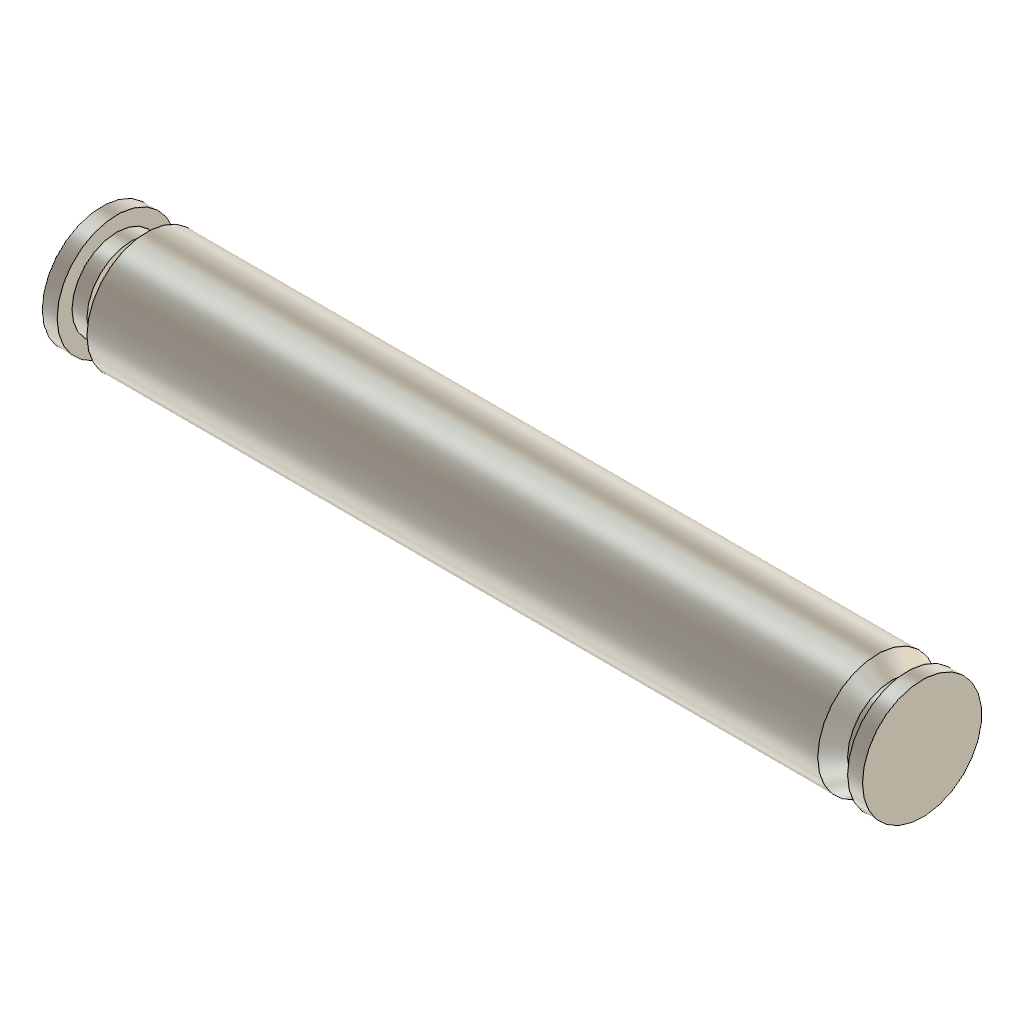
Full_V2_assembly_v81 (Autodesk Fusion 360 archive; units mm, degrees)
design "Foot_pin"
Autodesk Fusion 360 part; units mm, degrees
sketch "Sketch1" plane through (0, 0, 0) normal (1, 0, 0) x (0, 1, 0)
  circle A0 centre (0, 0) radius 4
  circle A1 centre (0, 0) radius 3
  dimension "d1" = 8
  dimension "d2" = 6
  constraint coincident A0.centre A1.centre
  measures "d1" diameter of A0
  measures "d2" diameter of A1
extrude "Extrude1" add sketch "Sketch1" along normal blind 55 contours A0 | A1
extrude "Extrude2" cut sketch "Sketch1" along normal blind 54
extrude "Extrude3" add sketch "Sketch1" along normal blind 53
extrude "Extrude4" cut sketch "Sketch1" along normal blind 2
extrude "Extrude5" add sketch "Sketch1" along normal blind 1
chamfer "Chamfer1" distance 1 angle 45 2 edges at (2, -3.7293, -1.4465) (53, -3.7293, -1.4465) tangent chain off

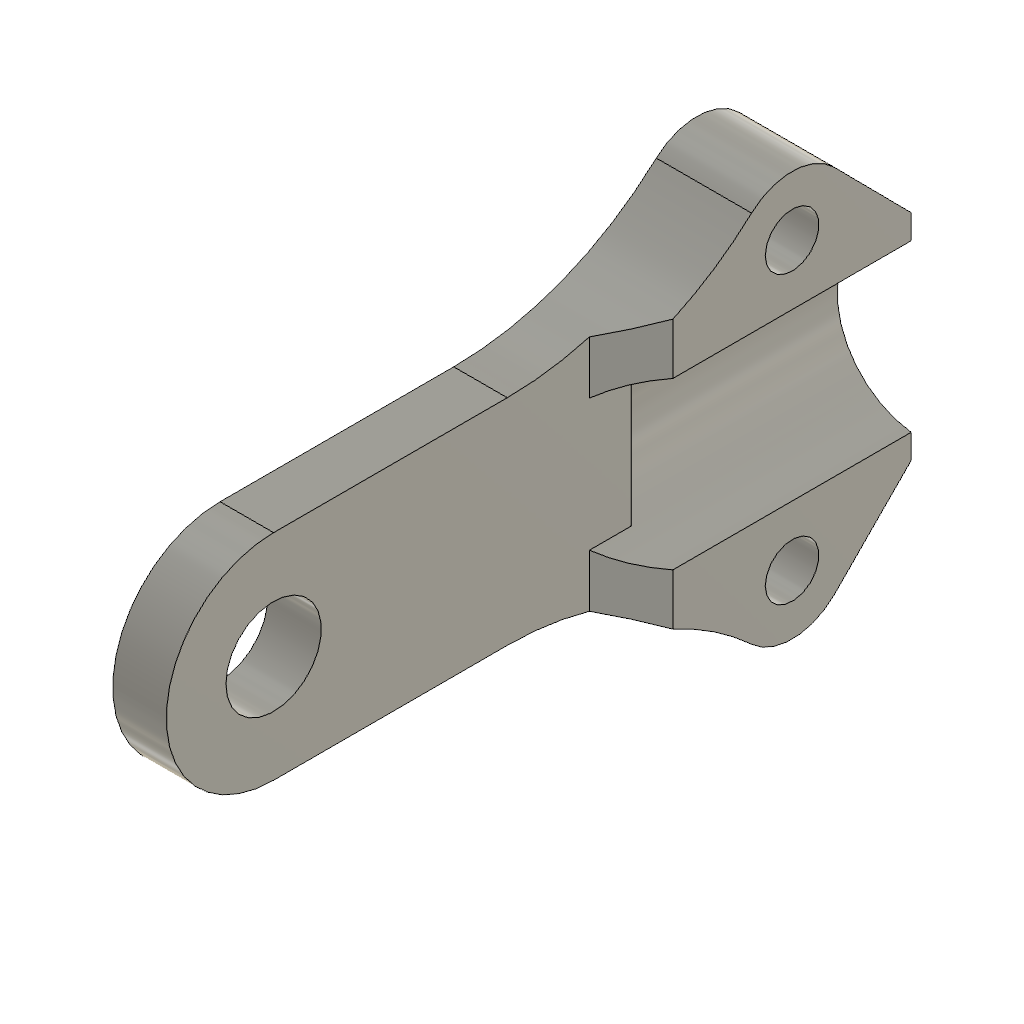
design "push_rod_cap"
Autodesk Fusion 360 part; units mm, degrees
sketch "Sketch1" plane through (0, 0, 0) normal (1, 0, 0) x (0, 1, 0)
  line L0 (30, -9) -> (30, 9)
  line L1 (0, -9) -> (0, 9)
  line L2 (30, 9) -> (36.445163, 15.516124)
  circle A0 centre (40, 12) radius 5
  circle A1 centre (40, 12) radius 2.25
  line L3 (50, 9) -> (50, -9)
  circle A2 centre (0, 0) radius 9
  line L4 (40, -9) -> (40, -12)
  line L5 (30, -9) -> (36.445163, -15.516124)
  line L6 (0, 9) -> (50, 9)
  line L7 (50, -9) -> (43.554837, -15.516124)
  circle A3 centre (0, 0) radius 4
  line L8 (50, 9) -> (50, -9)
  line L9 (50, 9) -> (43.554837, 15.516124)
  circle A4 centre (40, -12) radius 2.25
  line L10 (30, 9) -> (50, 9)
  circle A5 centre (40, -12) radius 5
  line L11 (50, -9) -> (30, -9)
  line L12 (50, -9) -> (0, -9)
  line L13 (40, 9) -> (40, 12)
  dimension "d1" = 8
  dimension "d2" = 18
  dimension "d3" = 50
  dimension "d4" = 4.5
  dimension "d5" = 20
  dimension "d6" = 3
  dimension "d7" = 3
  dimension "d8" = 4.5
  dimension "d9" = 10
  dimension "d10" = 10
  constraint coincident A2.centre A3.centre
  constraint concentric A2 A3
  constraint horizontal L6
  constraint vertical L8
  constraint horizontal L12
  constraint vertical L1
  constraint coincident L1.end A2
  constraint coincident L1.start A2
  constraint tangent A2 L12
  constraint horizontal L11
  constraint vertical L0
  constraint horizontal L10
  constraint vertical L3
  constraint midpoint L13.start L10
  constraint coincident A0.centre A1.centre
  constraint midpoint L4.start L11
  constraint perpendicular L4 L12
  constraint perpendicular L6 L13
  constraint coincident L4.end A4.centre
  constraint concentric A4 A5
  constraint collinear L6 L10
  constraint tangent L2 A0
  constraint tangent A0 L9
  constraint tangent L7 A5
  constraint tangent L5 A5
  measures "d1" diameter of A3
  measures "d2" diameter of A2
  measures "d3" distance of L1.end L3.start
  measures "d4" diameter of A1
  measures "d5" distance of L3.end L0.start
  measures "d6" distance of L4.start L4.end
  measures "d7" vertical distance of L13.start A0.centre
  measures "d8" diameter of A4
  measures "d9" diameter of A5
  measures "d10" diameter of A0
extrude "Extrude1" add sketch "Sketch1" along normal blind 4.5 contours L0 A2 L6 L12 | L1 A2 A3 | L1 A2 A3 picked at (23, 0) picked at (-6.545398, -3.26269) picked at (7.302798, -0.426945)
extrude "Extrude2" add sketch "Sketch1" along normal blind 8 contours L5 A5 L11 L12 | L0 A0 L3 L6 L8 L10 A5 L11 L12 | L2 A0 L6 L10 | A5 L11 L12 | A5 L11 L12 | A0 L6 L10 | A0 L6 L10 | L7 A5 L11 L12 | A0 L6 L9 L10 picked at (33.478377, -10.056745) picked at (47.664629, 2.665141) picked at (33.478377, 10.056745) picked at (38.346, -9.322008) picked at (40, -7.675143) picked at (38.346, 9.322008) picked at (40, 7.675143) picked at (46.489066, -9.948089) picked at (46.489066, 9.948089)
sketch "Sketch2" plane through (0, 50, 0) normal (0, 1, 0) x (-1, 0, 0)
  line L0 (0, -9) -> (0, 9)
  line L1 (0, 9) -> (-8, 9)
  line L2 (-8, 9) -> (-8, -9)
  line L3 (-8, -9) -> (0, -9)
  circle A0 centre (-8.8, 0) radius 7
  circle A1 centre (-8.8, 0) radius 6
  line L4 (0, 9) -> (0, -9)
  dimension "d15" = 14
  dimension "d16" = 12
  dimension "d17" = 8.8
  constraint concentric A0 A1
  measures "d15" diameter of A0
  measures "d16" diameter of A1
  measures "d17" distance of A0.centre L4
extrude "Extrude3" cut sketch "Sketch2" against normal blind 20 contours L2 A0 A1 | L2 A1 picked at (-7.666447, -6.555) picked at (-7.196087, 1.689337)
chamfer "Chamfer1" distance 3.5 angle 45 2 edges at (4.5, 30, 7.261793) (4.5, 30, -7.261793) tangent chain off
fillet "Fillet1" radius 25 2 edges at (4, 30, -9) (4, 30, 9)

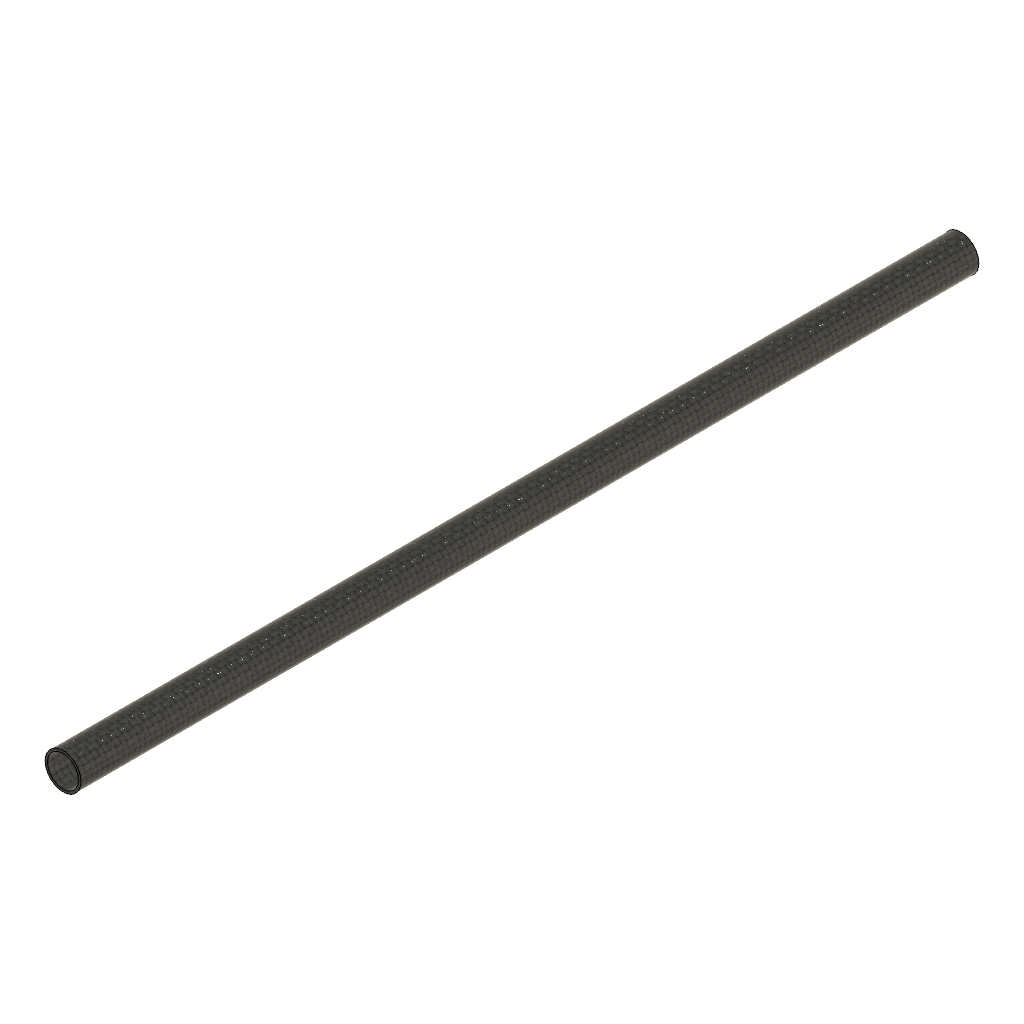
design "push_rod_carbon"
Autodesk Fusion 360 part; units mm, degrees
sketch "Sketch1" plane through (0, 0, 0) normal (0, 1, 0) x (1, 0, 0)
  circle A0 centre (0, 0) radius 7
  circle A1 centre (0, 0) radius 6
  dimension "d1" = 14
  dimension "d2" = 12
  constraint coincident A0.centre A1.centre
  constraint concentric A0 A1
  measures "d1" diameter of A0
  measures "d2" diameter of A1
extrude "Extrude1" add sketch "Sketch1" along normal blind 350

design "Push_rod_pin"
Autodesk Fusion 360 part; units mm, degrees
sketch "sketch 384" plane through (0, 0, 0) normal (-1, 0, 0) x (0, -1, 0)
  circle A0 centre (0, 0) radius 4
  circle A1 centre (0, 0) radius 4
extrude "Extrude1" add sketch "sketch 384" against normal blind 17.6
chamfer "Chamfer1" distance 1 angle 45 2 edges at (17.6, 3.7293, 1.4465) (0, 3.7293, -1.4465) tangent chain off
